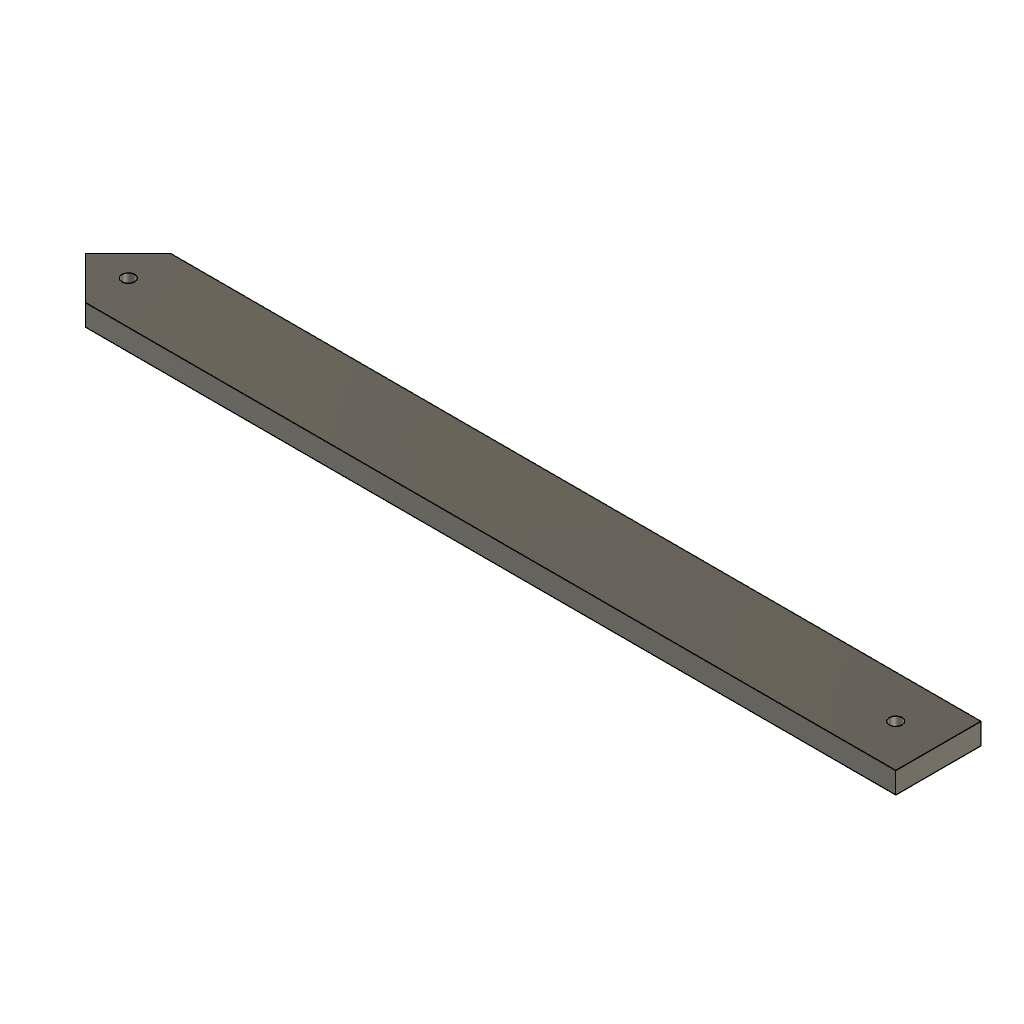
Base_x4 (Autodesk Fusion 360 design; units mm, degrees)
part number: 2026-09-25-16-32-48-181
Autodesk Fusion 360 part; units mm, degrees
sketch "Boceto1" plane through (0, 0, 0) normal (0, 0, 1) x (1, 0, 0)
  line L0 (0, 0) -> (200, 0)
  line L1 (200, 0) -> (200, 20)
  line L2 (200, 20) -> (0, 20)
  line L3 (0, 20) -> (0, 0)
  circle A0 centre (10, 10) radius 1.5
  line L4 (10, 0) -> (0, 10)
  line L5 (10, 20) -> (0, 10)
  circle A1 centre (190, 10) radius 1.5
  dimension "d1" = 200
  dimension "d2" = 20
  dimension "d3" = 3
  dimension "d4" = 10
  dimension "d5" = 10
  dimension "d6" = 3
  dimension "d7" = 10
  dimension "d8" = 10
  constraint horizontal L0
  constraint vertical L1
  constraint horizontal L2
  constraint vertical L3
  constraint coincident L0.start L3.end
  constraint coincident L0 L4.start
  constraint midpoint L3 L4.end
  constraint coincident L2 L5.start
  constraint perpendicular L4 L5
  measures "d1" distance of L1.end L2.end
  measures "d2" distance of L0.end L1.end
  measures "d3" diameter of A0
  measures "d4" distance of L2 A0.centre
  measures "d5" distance of L3 A0.centre
  measures "d6" diameter of A1
  measures "d7" distance of L1 A1.centre
  measures "d8" distance of L2 A1.centre
extrude "Extruir1" add sketch "Boceto1" along normal blind 5 contours L0 L1 L2 L4 L5
